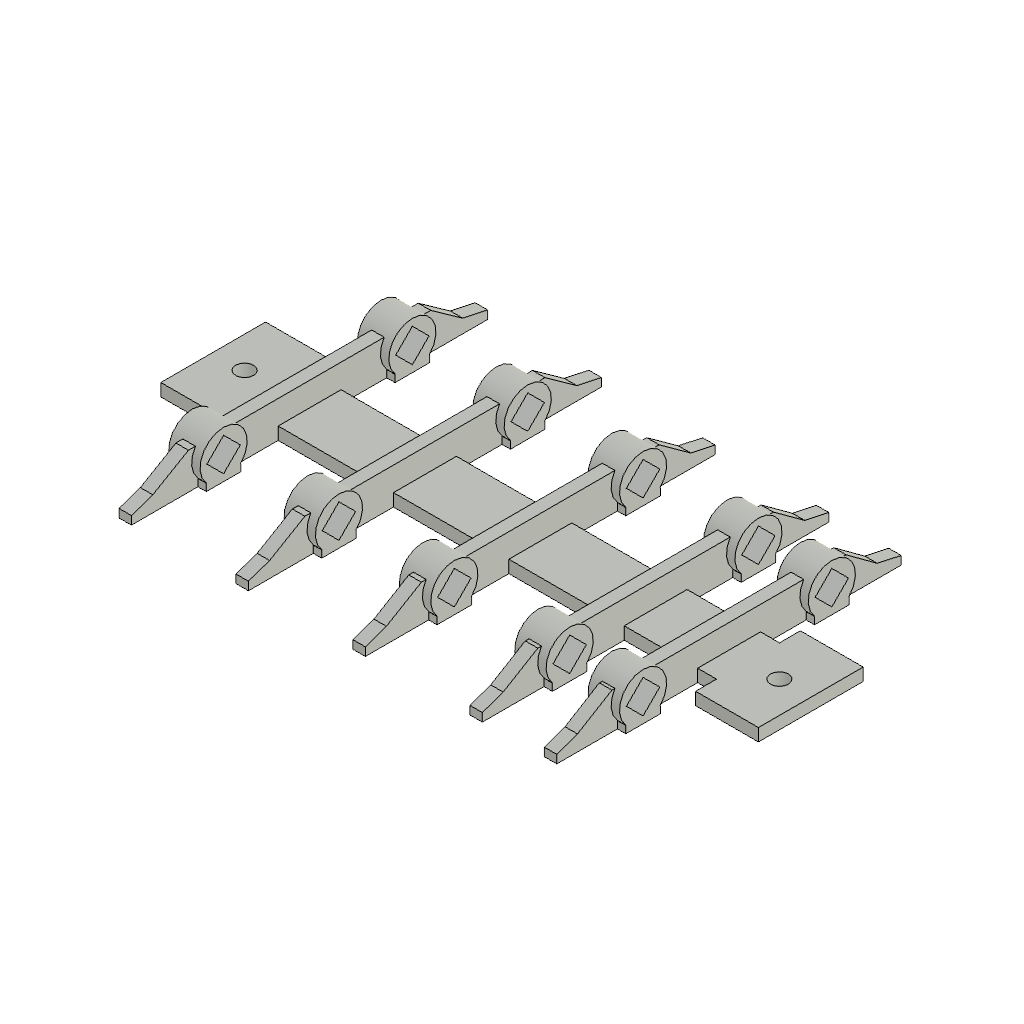
wing_middle (Autodesk Fusion 360 design; units mm, degrees)
part number: 2026-10-10-17-06-18-322
Autodesk Fusion 360 part; units mm, degrees
sketch "Continuous connecting strip sketch" plane through (0, 0, 0) normal (0, 0, 1) x (1, 0, 0)
  line L0 (0, -6) -> (114, -6)
  line L1 (114, -6) -> (114, 6)
  line L2 (114, 6) -> (0, 6)
  line L3 (0, 6) -> (0, -6)
extrude "Continuous connecting strip" add sketch "Continuous connecting strip sketch" along normal blind 2.4
ref_plane "WorkPlane1" through (16, 0, 0) normal (1, 0, 0) x (0, 1, 0)
sketch "Rib at 16 mm sketch" plane through (16, 0, 0) normal (1, 0, 0) x (0, 0, -1)
  line L0 (0, -33.977) -> (0, 33.977)
  line L1 (0, 33.977) -> (-1.6, 33.977)
  line L2 (-1.6, 33.977) -> (-2.6, 29.2202)
  line L3 (-2.6, 29.2202) -> (-6.95, 23.1044)
  line L4 (-6.95, 23.1044) -> (-6.95, -23.1044)
  line L5 (-6.95, -23.1044) -> (-3, -29.8998)
  line L6 (-3, -29.8998) -> (-1.6, -33.977)
  line L7 (-1.6, -33.977) -> (0, -33.977)
extrude "Rib at 16 mm" add sketch "Rib at 16 mm sketch" along normal blind 2.4
ref_plane "WorkPlane2" through (14, 0, 0) normal (1, 0, 0) x (0, 1, 0)
sketch "front short guide at 16 mm sketch" plane through (14, 0, 0) normal (1, 0, 0) x (0, 0, -1)
  circle A0 centre (-4.5, -18) radius 4.5
extrude "front short guide at 16 mm" add sketch "front short guide at 16 mm sketch" along normal blind 6
sketch "front guide foot at 16 mm sketch" plane through (0, 0, 0) normal (0, 0, 1) x (1, 0, 0)
  line L0 (14, -21.3) -> (20, -21.3)
  line L1 (20, -21.3) -> (20, -14.7)
  line L2 (20, -14.7) -> (14, -14.7)
  line L3 (14, -14.7) -> (14, -21.3)
extrude "front guide foot at 16 mm" add sketch "front guide foot at 16 mm sketch" along normal blind 1.4
ref_plane "WorkPlane3" through (14, 0, 0) normal (1, 0, 0) x (0, 1, 0)
sketch "rear short guide at 16 mm sketch" plane through (14, 0, 0) normal (1, 0, 0) x (0, 0, -1)
  circle A0 centre (-4.5, 18) radius 4.5
extrude "rear short guide at 16 mm" add sketch "rear short guide at 16 mm sketch" along normal blind 6
sketch "rear guide foot at 16 mm sketch" plane through (0, 0, 0) normal (0, 0, 1) x (1, 0, 0)
  line L0 (14, 14.7) -> (20, 14.7)
  line L1 (20, 14.7) -> (20, 21.3)
  line L2 (20, 21.3) -> (14, 21.3)
  line L3 (14, 21.3) -> (14, 14.7)
extrude "rear guide foot at 16 mm" add sketch "rear guide foot at 16 mm sketch" along normal blind 1.4
ref_plane "WorkPlane4" through (38, 0, 0) normal (1, 0, 0) x (0, 1, 0)
sketch "Rib at 38 mm sketch" plane through (38, 0, 0) normal (1, 0, 0) x (0, 0, -1)
  line L0 (0, -33.6684) -> (0, 33.6684)
  line L1 (0, 33.6684) -> (-1.6, 33.6684)
  line L2 (-1.6, 33.6684) -> (-2.6, 28.9548)
  line L3 (-2.6, 28.9548) -> (-6.95, 22.8945)
  line L4 (-6.95, 22.8945) -> (-6.95, -22.8945)
  line L5 (-6.95, -22.8945) -> (-3, -29.6281)
  line L6 (-3, -29.6281) -> (-1.6, -33.6684)
  line L7 (-1.6, -33.6684) -> (0, -33.6684)
extrude "Rib at 38 mm" add sketch "Rib at 38 mm sketch" along normal blind 2.4
ref_plane "WorkPlane5" through (36, 0, 0) normal (1, 0, 0) x (0, 1, 0)
sketch "front short guide at 38 mm sketch" plane through (36, 0, 0) normal (1, 0, 0) x (0, 0, -1)
  circle A0 centre (-4.5, -18) radius 4.5
extrude "front short guide at 38 mm" add sketch "front short guide at 38 mm sketch" along normal blind 6
sketch "front guide foot at 38 mm sketch" plane through (0, 0, 0) normal (0, 0, 1) x (1, 0, 0)
  line L0 (36, -21.3) -> (42, -21.3)
  line L1 (42, -21.3) -> (42, -14.7)
  line L2 (42, -14.7) -> (36, -14.7)
  line L3 (36, -14.7) -> (36, -21.3)
extrude "front guide foot at 38 mm" add sketch "front guide foot at 38 mm sketch" along normal blind 1.4
ref_plane "WorkPlane6" through (36, 0, 0) normal (1, 0, 0) x (0, 1, 0)
sketch "rear short guide at 38 mm sketch" plane through (36, 0, 0) normal (1, 0, 0) x (0, 0, -1)
  circle A0 centre (-4.5, 18) radius 4.5
extrude "rear short guide at 38 mm" add sketch "rear short guide at 38 mm sketch" along normal blind 6
sketch "rear guide foot at 38 mm sketch" plane through (0, 0, 0) normal (0, 0, 1) x (1, 0, 0)
  line L0 (36, 14.7) -> (42, 14.7)
  line L1 (42, 14.7) -> (42, 21.3)
  line L2 (42, 21.3) -> (36, 21.3)
  line L3 (36, 21.3) -> (36, 14.7)
extrude "rear guide foot at 38 mm" add sketch "rear guide foot at 38 mm sketch" along normal blind 1.4
ref_plane "WorkPlane7" through (60, 0, 0) normal (1, 0, 0) x (0, 1, 0)
sketch "Rib at 60 mm sketch" plane through (60, 0, 0) normal (1, 0, 0) x (0, 0, -1)
  line L0 (0, -33.3597) -> (0, 33.3597)
  line L1 (0, 33.3597) -> (-1.6, 33.3597)
  line L2 (-1.6, 33.3597) -> (-2.6, 28.6893)
  line L3 (-2.6, 28.6893) -> (-6.95, 22.6846)
  line L4 (-6.95, 22.6846) -> (-6.95, -22.6846)
  line L5 (-6.95, -22.6846) -> (-3, -29.3565)
  line L6 (-3, -29.3565) -> (-1.6, -33.3597)
  line L7 (-1.6, -33.3597) -> (0, -33.3597)
extrude "Rib at 60 mm" add sketch "Rib at 60 mm sketch" along normal blind 2.4
ref_plane "WorkPlane8" through (58, 0, 0) normal (1, 0, 0) x (0, 1, 0)
sketch "front short guide at 60 mm sketch" plane through (58, 0, 0) normal (1, 0, 0) x (0, 0, -1)
  circle A0 centre (-4.5, -18) radius 4.5
extrude "front short guide at 60 mm" add sketch "front short guide at 60 mm sketch" along normal blind 6
sketch "front guide foot at 60 mm sketch" plane through (0, 0, 0) normal (0, 0, 1) x (1, 0, 0)
  line L0 (58, -21.3) -> (64, -21.3)
  line L1 (64, -21.3) -> (64, -14.7)
  line L2 (64, -14.7) -> (58, -14.7)
  line L3 (58, -14.7) -> (58, -21.3)
extrude "front guide foot at 60 mm" add sketch "front guide foot at 60 mm sketch" along normal blind 1.4
ref_plane "WorkPlane9" through (58, 0, 0) normal (1, 0, 0) x (0, 1, 0)
sketch "rear short guide at 60 mm sketch" plane through (58, 0, 0) normal (1, 0, 0) x (0, 0, -1)
  circle A0 centre (-4.5, 18) radius 4.5
extrude "rear short guide at 60 mm" add sketch "rear short guide at 60 mm sketch" along normal blind 6
sketch "rear guide foot at 60 mm sketch" plane through (0, 0, 0) normal (0, 0, 1) x (1, 0, 0)
  line L0 (58, 14.7) -> (64, 14.7)
  line L1 (64, 14.7) -> (64, 21.3)
  line L2 (64, 21.3) -> (58, 21.3)
  line L3 (58, 21.3) -> (58, 14.7)
extrude "rear guide foot at 60 mm" add sketch "rear guide foot at 60 mm sketch" along normal blind 1.4
ref_plane "WorkPlane10" through (82, 0, 0) normal (1, 0, 0) x (0, 1, 0)
sketch "Rib at 82 mm sketch" plane through (82, 0, 0) normal (1, 0, 0) x (0, 0, -1)
  line L0 (0, -33.0511) -> (0, 33.0511)
  line L1 (0, 33.0511) -> (-1.6, 33.0511)
  line L2 (-1.6, 33.0511) -> (-2.6, 28.4239)
  line L3 (-2.6, 28.4239) -> (-6.95, 22.4747)
  line L4 (-6.95, 22.4747) -> (-6.95, -22.4747)
  line L5 (-6.95, -22.4747) -> (-3, -29.0849)
  line L6 (-3, -29.0849) -> (-1.6, -33.0511)
  line L7 (-1.6, -33.0511) -> (0, -33.0511)
extrude "Rib at 82 mm" add sketch "Rib at 82 mm sketch" along normal blind 2.4
ref_plane "WorkPlane11" through (80, 0, 0) normal (1, 0, 0) x (0, 1, 0)
sketch "front short guide at 82 mm sketch" plane through (80, 0, 0) normal (1, 0, 0) x (0, 0, -1)
  circle A0 centre (-4.5, -18) radius 4.5
extrude "front short guide at 82 mm" add sketch "front short guide at 82 mm sketch" along normal blind 6
sketch "front guide foot at 82 mm sketch" plane through (0, 0, 0) normal (0, 0, 1) x (1, 0, 0)
  line L0 (80, -21.3) -> (86, -21.3)
  line L1 (86, -21.3) -> (86, -14.7)
  line L2 (86, -14.7) -> (80, -14.7)
  line L3 (80, -14.7) -> (80, -21.3)
extrude "front guide foot at 82 mm" add sketch "front guide foot at 82 mm sketch" along normal blind 1.4
ref_plane "WorkPlane12" through (80, 0, 0) normal (1, 0, 0) x (0, 1, 0)
sketch "rear short guide at 82 mm sketch" plane through (80, 0, 0) normal (1, 0, 0) x (0, 0, -1)
  circle A0 centre (-4.5, 18) radius 4.5
extrude "rear short guide at 82 mm" add sketch "rear short guide at 82 mm sketch" along normal blind 6
sketch "rear guide foot at 82 mm sketch" plane through (0, 0, 0) normal (0, 0, 1) x (1, 0, 0)
  line L0 (80, 14.7) -> (86, 14.7)
  line L1 (86, 14.7) -> (86, 21.3)
  line L2 (86, 21.3) -> (80, 21.3)
  line L3 (80, 21.3) -> (80, 14.7)
extrude "rear guide foot at 82 mm" add sketch "rear guide foot at 82 mm sketch" along normal blind 1.4
ref_plane "WorkPlane13" through (96, 0, 0) normal (1, 0, 0) x (0, 1, 0)
sketch "Rib at 96 mm sketch" plane through (96, 0, 0) normal (1, 0, 0) x (0, 0, -1)
  line L0 (0, -32.8547) -> (0, 32.8547)
  line L1 (0, 32.8547) -> (-1.6, 32.8547)
  line L2 (-1.6, 32.8547) -> (-2.6, 28.255)
  line L3 (-2.6, 28.255) -> (-6.95, 22.3412)
  line L4 (-6.95, 22.3412) -> (-6.95, -22.3412)
  line L5 (-6.95, -22.3412) -> (-3, -28.9121)
  line L6 (-3, -28.9121) -> (-1.6, -32.8547)
  line L7 (-1.6, -32.8547) -> (0, -32.8547)
extrude "Rib at 96 mm" add sketch "Rib at 96 mm sketch" along normal blind 2.4
ref_plane "WorkPlane14" through (94, 0, 0) normal (1, 0, 0) x (0, 1, 0)
sketch "front short guide at 96 mm sketch" plane through (94, 0, 0) normal (1, 0, 0) x (0, 0, -1)
  circle A0 centre (-4.5, -18) radius 4.5
extrude "front short guide at 96 mm" add sketch "front short guide at 96 mm sketch" along normal blind 6
sketch "front guide foot at 96 mm sketch" plane through (0, 0, 0) normal (0, 0, 1) x (1, 0, 0)
  line L0 (94, -21.3) -> (100, -21.3)
  line L1 (100, -21.3) -> (100, -14.7)
  line L2 (100, -14.7) -> (94, -14.7)
  line L3 (94, -14.7) -> (94, -21.3)
extrude "front guide foot at 96 mm" add sketch "front guide foot at 96 mm sketch" along normal blind 1.4
ref_plane "WorkPlane15" through (94, 0, 0) normal (1, 0, 0) x (0, 1, 0)
sketch "rear short guide at 96 mm sketch" plane through (94, 0, 0) normal (1, 0, 0) x (0, 0, -1)
  circle A0 centre (-4.5, 18) radius 4.5
extrude "rear short guide at 96 mm" add sketch "rear short guide at 96 mm sketch" along normal blind 6
sketch "rear guide foot at 96 mm sketch" plane through (0, 0, 0) normal (0, 0, 1) x (1, 0, 0)
  line L0 (94, 14.7) -> (100, 14.7)
  line L1 (100, 14.7) -> (100, 21.3)
  line L2 (100, 21.3) -> (94, 21.3)
  line L3 (94, 21.3) -> (94, 14.7)
extrude "rear guide foot at 96 mm" add sketch "rear guide foot at 96 mm sketch" along normal blind 1.4
sketch "Joint landing at 0 sketch" plane through (0, 0, 0) normal (0, 0, 1) x (1, 0, 0)
  line L0 (0, -10) -> (12, -10)
  line L1 (12, -10) -> (12, 10)
  line L2 (12, 10) -> (0, 10)
  line L3 (0, 10) -> (0, -10)
extrude "Joint landing at 0" add sketch "Joint landing at 0 sketch" along normal blind 2.4
ref_plane "WorkPlane16" through (0, 0, -0.05) normal (0, 0, 1) x (1, 0, 0)
sketch "Joint bolt at 6 sketch" plane through (0, 0, -0.05) normal (0, 0, 1) x (1, 0, 0)
  circle A0 centre (6, 0) radius 1.7
  dimension "d229" = 3.4
  measures "d229" diameter of A0
extrude "Joint bolt at 6" cut sketch "Joint bolt at 6 sketch" along normal blind 2.5
sketch "Joint landing at 102.0 sketch" plane through (0, 0, 0) normal (0, 0, 1) x (1, 0, 0)
  line L0 (102, -10) -> (114, -10)
  line L1 (114, -10) -> (114, 10)
  line L2 (114, 10) -> (102, 10)
  line L3 (102, 10) -> (102, -10)
extrude "Joint landing at 102.0" add sketch "Joint landing at 102.0 sketch" along normal blind 2.4
ref_plane "WorkPlane17" through (0, 0, -0.05) normal (0, 0, 1) x (1, 0, 0)
sketch "Joint bolt at 108.0 sketch" plane through (0, 0, -0.05) normal (0, 0, 1) x (1, 0, 0)
  circle A0 centre (108, 0) radius 1.7
  dimension "d236" = 3.4
  measures "d236" diameter of A0
extrude "Joint bolt at 108.0" cut sketch "Joint bolt at 108.0 sketch" along normal blind 2.5
ref_plane "WorkPlane18" through (-0.05, 0, 0) normal (1, 0, 0) x (0, 1, 0)
sketch "front diamond bamboo passage sketch" plane through (-0.05, 0, 0) normal (1, 0, 0) x (0, 0, -1)
  line L0 (-4.5, -21.182) -> (-1.318, -18)
  line L1 (-1.318, -18) -> (-4.5, -14.818)
  line L2 (-4.5, -14.818) -> (-7.682, -18)
  line L3 (-7.682, -18) -> (-4.5, -21.182)
  line L4 (-4.5, -21.182) -> (-4.5, -14.818) construction
  line L5 (-1.318, -18) -> (-7.682, -18) construction
  point P0 (-4.5, -18)
  dimension "d241" = 6.364
  constraint vertical L4
  constraint horizontal L5
  constraint midpoint L4 P0
  constraint midpoint L5 P0
  constraint equal L4 L5
  measures "d241" distance of L0.end L2.end
extrude "front diamond bamboo passage" cut sketch "front diamond bamboo passage sketch" along normal blind 114.1
ref_plane "WorkPlane19" through (-0.05, 0, 0) normal (1, 0, 0) x (0, 1, 0)
sketch "rear diamond bamboo passage sketch" plane through (-0.05, 0, 0) normal (1, 0, 0) x (0, 0, -1)
  line L0 (-4.5, 14.818) -> (-1.318, 18)
  line L1 (-1.318, 18) -> (-4.5, 21.182)
  line L2 (-4.5, 21.182) -> (-7.682, 18)
  line L3 (-7.682, 18) -> (-4.5, 14.818)
  line L4 (-4.5, 14.818) -> (-4.5, 21.182) construction
  line L5 (-1.318, 18) -> (-7.682, 18) construction
  point P0 (-4.5, 18)
  dimension "d246" = 6.364
  constraint vertical L4
  constraint horizontal L5
  constraint midpoint L4 P0
  constraint midpoint L5 P0
  constraint equal L4 L5
  measures "d246" distance of L0.end L2.end
extrude "rear diamond bamboo passage" cut sketch "rear diamond bamboo passage sketch" along normal blind 114.1
equation "d143 = spanStripThickness"
equation "d225 = spanStripThickness"
equation "d229 = m3Clearance"
equation "d232 = spanStripThickness"
equation "d236 = m3Clearance"
equation "d241 = sparBore * sqrt(2)"
equation "d246 = sparBore * sqrt(2)"
equation "sparDiameter = 4 mm" comment "Nominal bamboo diameter; choose clearance with fit coupon"
equation "sparClearance = 0.5 mm" comment "Diametral clearance; 4.5 mm coupon fit selected by user"
equation "sparBore = sparDiameter + sparClearance" comment "Flat-to-flat width of all six native diamond passages"
equation "m3Clearance = 3.4 mm" comment "Root registration and tip adapter holes"
equation "spanStripThickness = 2.4 mm" comment "Middle, tip and reinforced joint-end thickness"
named bodies: "wing_middle - printable solid"
